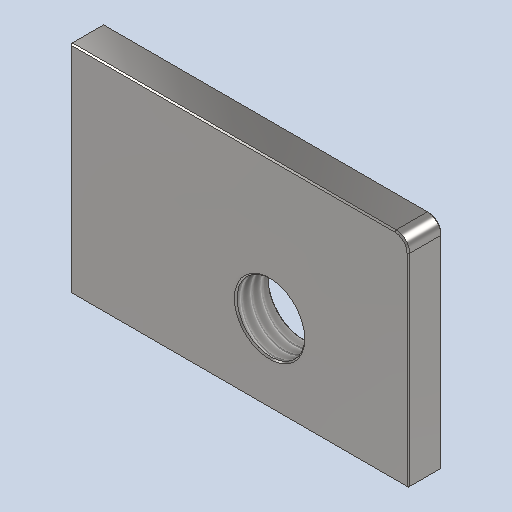
# Autodesk Inventor part: EInspannvorrichtung Befestigunsplatte
Saved by Autodesk Inventor 2026.2 (Build 302298010, 298A)
## iProperties
Created: 2026-07-28
Part Number: EInspannvorrichtung Befestigunsplatte
Material: Stahl, Legierung
Document SubType Name: Modeling
Designer: moest
Density: 7.73 g/cm^3
Appearance: Halbpoliert
Author: moest
Autodesk Inventor part; units mm, degrees
ref_plane "YZ Plane" through (0, 0, 0) normal (1, 0, 0) x (0, 1, 0)
ref_plane "XZ Plane" through (0, 0, 0) normal (0, 1, 0) x (-1, 0, 0)
ref_plane "XY Plane" through (0, 0, 0) normal (0, 0, 1) x (1, 0, 0)
sketch "Skizze1" plane through (0, 0, 0) normal (0, 1, 0) x (-1, 0, 0)
  line L0 (0, 0) -> (50, 0)
  line L1 (50, 0) -> (50, -32)
  line L2 (50, -32) -> (0, -32)
  line L3 (0, -32) -> (0, 0)
  dimension "d0" = 50
  dimension "d1" = 32
  constraints: 8 end point, 2 parallel, 1 horizontal, 1 perpendicular
  measures "d0" distance of L1.end L2.end
  measures "d1" distance of L0.end L1.end
extrude "Extrusion1" add sketch "Skizze1" along normal blind 5
fillet "Rundung1" radius 2 1 edges at (0, 2.5, 0)
sketch "Skizze2" plane through (0, 5, 0) normal (0, 1, 0) x (1, 0, 0)
  circle A0 centre (-20.5, 20.5) radius 5
  line L0 (-50, 0) -> (-2, 0) projected
  line L1 (0, 2) -> (0, 32) projected
  point P0 (0, 0)
  dimension "d5" = 20.5
  dimension "d6" = 20.5
  dimension "d7" = 10
  constraints: 1 centre point
  measures "d5" distance from line of A0.centre L0
  measures "d6" distance from line of L1 A0.centre
  measures "d7" diameter of A0
extrude "Extrusion2" cut sketch "Skizze2" against normal blind 5
thread "Gewinde1" size "M10x1.5" class "6H" standard "ANSI Metric M Profile" full length
chamfer "Fasen1" distance 0.2 angle 45 15 edges at (-25.5, 0, -20.5) (-25.5, 5, -20.5) (-50, 2.5, 0) (-26, 0, 0) (-0.5858, 0, -0.5858) (0, 0, -17) (-26, 5, 0) (-0.5858, 5, -0.5858) (0, 5, -17) (-50, 0, -16) (-50, 5, -16) (-50, 2.5, -32) (-25, 5, -32) (-25, 0, -32) (0, 2.5, -32)
